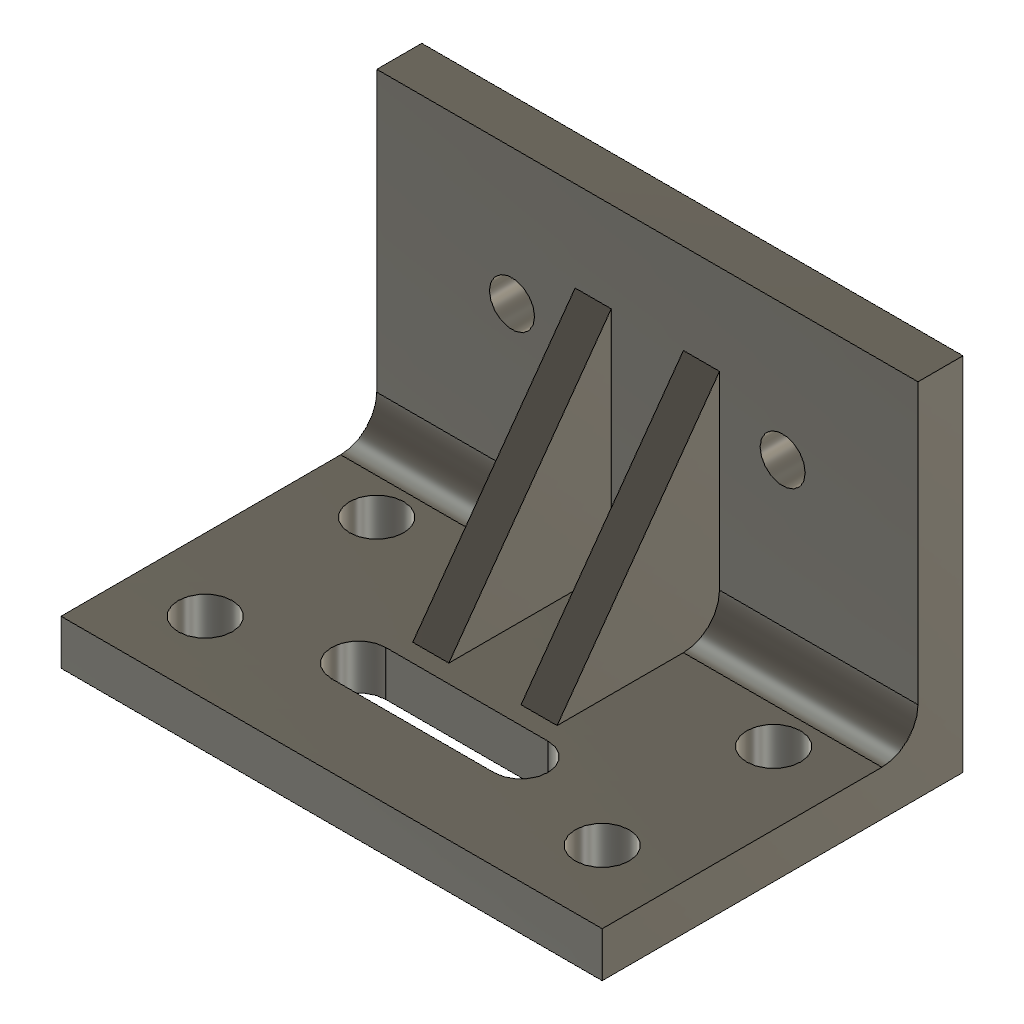
feeder_bracket_model1_good (Autodesk Fusion 360 design; units mm, degrees)
part number: 2026-10-23-15-36-10-933
Autodesk Fusion 360 part; units mm, degrees
sketch "Base" plane through (0, 0, 0) normal (0, 0, 1) x (1, 0, 0)
  line L0 (0, 0) -> (60, 0)
  line L1 (60, 0) -> (60, 40)
  line L2 (60, 40) -> (0, 40)
  line L3 (0, 40) -> (0, 0)
  dimension "d6" = 60
  dimension "d7" = 40
  constraint coincident L0.start L3.end
  measures "d6" horizontal distance of L0.start L0.end
  measures "d7" vertical distance of L0.start L2.end
extrude "Base_Plate" add sketch "Base" along normal blind 5
sketch "Wall" plane through (0, 0, 0) normal (0, 0, 1) x (1, 0, 0)
  line L0 (0, 35) -> (60, 35)
  line L1 (60, 35) -> (60, 40)
  line L2 (60, 40) -> (0, 40)
  line L3 (0, 40) -> (0, 35)
  line L4 (0, 1.75) -> (0, 22.5) construction
  dimension "d10" = 60
  dimension "d11" = 5
  dimension "d12" = 40
  constraint coincident L2.end L4
  constraint coincident L0.start L4
  measures "d10" horizontal distance of L1.end L2.end
  measures "d11" vertical distance of L0.start L2.end
  measures "d12" vertical distance of origin L2.end
extrude "Vertical_Plate" add sketch "Wall" along normal blind 40
fillet "Inner_Fillet" radius 4 1 edges at (30, 35, 5)
sketch "Base_Holes" plane through (0, 0, 0) normal (0, 0, 1) x (1, 0, 0)
  circle A0 centre (8, 8) radius 3
  circle A1 centre (52, 8) radius 3
  circle A2 centre (8, 27) radius 3
  circle A3 centre (52, 27) radius 3
extrude "Base_Holes (1)" cut sketch "Base_Holes" along normal through all
sketch "Center_Slot" plane through (0, 0, 0) normal (0, 0, 1) x (1, 0, 0)
  line L0 (21, 9) -> (39, 9)
  line L1 (39, 15) -> (21, 15)
  arc A0 (39, 9) -> (39, 15) centre (39, 12) ccw
  arc A1 (21, 15) -> (21, 9) centre (21, 12) ccw
extrude "Center_Slot (1)" cut sketch "Center_Slot" along normal through all
sketch "Wall_Holes" plane through (0, 0, 0) normal (0, 1, 0) x (1, 0, 0)
  circle A0 centre (15, -25) radius 2.5
  circle A1 centre (45, -25) radius 2.5
extrude "Wall_Holes (1)" cut sketch "Wall_Holes" against normal through all
sketch "Gusset_Profile" plane through (0, 0, 0) normal (1, 0, 0) x (0, 0, -1)
  line L0 (-5, 17) -> (-5, 35)
  line L1 (-5, 35) -> (-30, 35)
  line L2 (-30, 35) -> (-5, 17)
extrude "Gusset_1" add sketch "Gusset_Profile" along normal blind 4 from surface at 22
extrude "Gusset_2" add sketch "Gusset_Profile" along normal blind 4 from surface at 34
equation "base_w = 60 mm"
equation "base_d = 40 mm"
equation "base_t = 5 mm"
equation "wall_h = 40 mm"
equation "wall_t = 5 mm"
equation "d6 = base_w"
equation "d7 = base_d"
equation "d8 = base_t"
equation "d10 = base_w"
equation "d11 = wall_t"
equation "d12 = base_d"
equation "d13 = wall_h"
named bodies: "Feeder_Bracket_M1"
